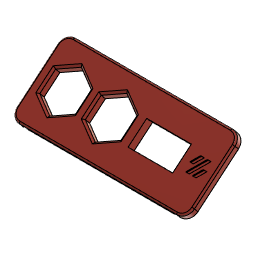
VoronSSD1306FrontScreen (Autodesk Fusion 360 design; units mm, degrees)
Autodesk Fusion 360 part; units mm, degrees
sketch "Skizze1" plane through (0, 0, 0) normal (0, 0, 1) x (1, 0, 0)
  line L0 (6, 0) -> (103, 0)
  line L1 (109, 6) -> (109, 38.6)
  line L2 (103, 44.6) -> (6, 44.6)
  line L3 (0, 38.6) -> (0, 6)
  arc A0 (6, 44.6) -> (0, 38.6) centre (6, 38.6) ccw
  arc A1 (109, 38.6) -> (103, 44.6) centre (103, 38.6) ccw
  arc A2 (103, 0) -> (109, 6) centre (103, 6) ccw
  arc A3 (0, 6) -> (6, 0) centre (6, 6) ccw
  circle A4 centre (7.9, 42.85) radius 2.35
  circle A5 centre (7.9, 1.75) radius 2.35
  circle A6 centre (101.1, 1.75) radius 2.35
  circle A7 centre (101.1, 42.85) radius 2.35
  line L4 (89.5, 34.3) -> (62, 34.3)
  line L5 (62, 34.3) -> (62, 6.3)
  line L6 (62, 6.3) -> (89.5, 6.3)
  line L7 (89.5, 6.3) -> (89.5, 34.3)
  line L8 (89.5, 34.3) -> (62, 6.3) construction
  line L9 (62, 34.3) -> (89.5, 6.3) construction
  line L10 (62, 29.8) -> (89.5, 29.8)
  line L11 (62, 14.8) -> (89.5, 14.8)
  line L12 (89.5, 9.8) -> (84.5, 9.8)
  line L13 (84.5, 9.8) -> (84.5, 6.3)
  line L14 (62, 9.8) -> (67, 9.8)
  line L15 (67, 9.8) -> (67, 6.3)
  line L16 (6, 15.9295) -> (17, 9.5787)
  line L17 (28, 28.6312) -> (17, 34.9821)
  line L18 (28, 15.9295) -> (28, 28.6312)
  line L19 (6, 28.6312) -> (6, 15.9295)
  line L20 (17, 9.5787) -> (28, 15.9295)
  line L21 (17, 34.9821) -> (6, 28.6312)
  line L22 (56, 28.6825) -> (45, 35.0333)
  line L23 (34, 28.6825) -> (34, 15.9808)
  line L24 (45, 35.0333) -> (34, 28.6825)
  line L25 (34, 15.9808) -> (45, 9.6299)
  line L26 (56, 15.9808) -> (56, 28.6825)
  line L27 (45, 9.6299) -> (56, 15.9808)
  line L28 (182, 0.3509) -> (171, 6.7017)
  line L29 (160, 0.3509) -> (160, -12.3509)
  line L30 (171, 6.7017) -> (160, 0.3509)
  line L31 (160, -12.3509) -> (171, -18.7017)
  line L32 (182, -12.3509) -> (182, 0.3509)
  line L33 (171, -18.7017) -> (182, -12.3509)
  line L34 (94.9685, 18.0639) -> (101.1584, 27.4799)
  line L35 (103.4205, 27.4799) -> (97.2309, 18.0639)
  line L36 (97.2309, 18.0639) -> (94.9685, 18.0639)
  line L37 (101.1584, 27.4799) -> (103.4205, 27.4799)
  line L38 (96.9893, 27.4799) -> (99.2516, 27.4799)
  line L39 (96.1573, 22.772) -> (93.8945, 22.772)
  line L40 (93.8945, 22.772) -> (96.9893, 27.4799)
  line L41 (99.2516, 27.4799) -> (96.1573, 22.772)
  line L42 (99.1374, 18.0639) -> (102.2323, 22.772)
  line L43 (104.4949, 22.772) -> (101.4002, 18.0639)
  line L44 (102.2323, 22.772) -> (104.4949, 22.772)
  line L45 (101.4002, 18.0639) -> (99.1374, 18.0639)
  point P0 (109, 0)
  point P1 (0, 44.6)
  point P2 (75.75, 20.3)
  point P3 (17, 22.2804)
  point P4 (45, 22.3316)
  point P5 (171, -6)
  point P6 (99.1947, 22.7719)
  point P7 (31.9611, 46.5087)
  dimension "d1" = 109
  dimension "d2" = 44.6
  dimension "d7" = 6
  dimension "d8" = 4.7
  dimension "d9" = 1.75
  dimension "d10" = 7.9
  dimension "d11" = 4.7
  dimension "d12" = 4.7
  dimension "d13" = 4.7
  dimension "d14" = 7.9
  dimension "d15" = 1.75
  dimension "d16" = 1.75
  dimension "d17" = 7.9
  dimension "d18" = 7.9
  dimension "d19" = 1.75
  dimension "d24" = 27.5
  dimension "d25" = 28
  dimension "d26" = 15
  dimension "d28" = 5
  dimension "d29" = 5
  dimension "d30" = 4.5
  dimension "d31" = 5
  dimension "d32" = 5
  dimension "d34" = 11
  dimension "d38" = 11
  dimension "d39" = 11
  dimension "d53" = 14.8
  dimension "d56" = 6
  dimension "d57" = 6
  dimension "d59" = 6
  constraint horizontal L0
  constraint vertical L1
  constraint horizontal L2
  constraint vertical L3
  constraint coincident P1 L2
  constraint coincident P1 L3
  constraint tangent L2 A0
  constraint tangent L3 A0
  constraint tangent L1 A1
  constraint tangent L2 A1
  constraint equal A0 A1
  constraint coincident P0 L0
  constraint coincident P0 L1
  constraint tangent L0 A2
  constraint tangent L1 A2
  constraint equal A0 A2
  constraint coincident origin L0
  constraint coincident origin L3
  constraint tangent L0 A3
  constraint tangent L3 A3
  constraint equal A0 A3
  constraint horizontal L4
  constraint perpendicular L4 L5
  constraint parallel L4 L6
  constraint parallel L5 L7
  constraint coincident L8 P2
  constraint coincident L9 P2
  constraint coincident L5 L10.start
  constraint coincident L7 L10.end
  constraint perpendicular L7 L10
  constraint coincident L5 L11.start
  constraint coincident L7 L11.end
  constraint perpendicular L7 L11
  constraint coincident L7 L12.start
  constraint perpendicular L7 L12
  constraint coincident L6 L13.end
  constraint perpendicular L6 L13
  constraint coincident L5 L14.start
  constraint perpendicular L5 L14
  constraint coincident L6 L15.end
  constraint perpendicular L6 L15
  measures "d1" distance of origin P0
  measures "d2" distance of origin P1
  measures "d7" radius of A0
  measures "d8" diameter of A4
  measures "d9" distance of L2 A4.centre
  measures "d10" distance of L3 A4.centre
  measures "d11" diameter of A5
  measures "d12" diameter of A6
  measures "d13" diameter of A7
  measures "d14" distance of L3 A5.centre
  measures "d15" distance of L0 A5.centre
  measures "d16" distance of L0 A6.centre
  measures "d17" distance of L1 A6.centre
  measures "d18" distance of L1 A7.centre
  measures "d19" distance of L2 A7.centre
  measures "d24" distance of L5.end L6.end
  measures "d25" distance of L4.end L5.end
  measures "d26" distance of L10 L11
  measures "d28" distance of L12.start L12.end
  measures "d29" distance of L11 L12
  measures "d30" distance of L4 L10
  measures "d31" distance of L14.start L14.end
  measures "d32" distance of L11 L14
  measures "d34" distance of P3 L18
  measures "d38" distance of P4 L26
  measures "d39" distance of P5 L32
  measures "d53" distance of L2 L10
  measures "d56" distance of L5 L26
  measures "d57" distance of L18 L23
  measures "d59" distance of L3 L19
sketch "Skizze1 (2)" plane through (0, 0, 0) normal (0, 0, 1) x (1, 0, 0) in component "SSD1306"
  line L0 (0, 0) -> (27.5, 0)
  line L1 (27.5, 0) -> (27.5, 27.5)
  line L2 (27.5, 27.5) -> (0, 27.5)
  line L3 (0, 27.5) -> (0, 0)
  circle A0 centre (3.3, 25.5) radius 1.05
  line L4 (0, 23.5) -> (27.5, 23.5)
  line L5 (27.5, 23.5) -> (27.5, 1.5)
  line L6 (27.5, 1.5) -> (0, 1.5)
  line L7 (0, 1.5) -> (0, 23.5)
  line L8 (8.75, 26.989) -> (18.75, 26.989)
  line L9 (18.75, 26.989) -> (18.75, 23.989)
  line L10 (18.75, 23.989) -> (8.75, 23.989)
  line L11 (8.75, 23.989) -> (8.75, 26.989)
  dimension "d1_1" = 27.5
  dimension "d2_1" = 27.5
  dimension "d3_1" = 2.1
  dimension "d4_1" = 2
  dimension "d5_1" = 3.3
  dimension "d6_1" = 22
  dimension "d7_1" = 4
  dimension "d8_1" = 10
  dimension "d9_1" = 3
  dimension "d10_1" = 8.75
  constraint horizontal L0
  constraint vertical L1
  constraint horizontal L2
  constraint vertical L3
  constraint coincident L0.start L3.end
  constraint horizontal L4
  constraint vertical L5
  constraint horizontal L6
  constraint vertical L7
  constraint coincident L3 L4.start
  constraint horizontal L8
  constraint vertical L9
  constraint horizontal L10
  constraint vertical L11
  measures "d1_1" distance of L0.start L0.end
  measures "d2_1" distance of L0.start L2.end
  measures "d3_1" diameter of A0
  measures "d4_1" distance of L2 A0.centre
  measures "d5_1" distance of L3 A0.centre
  measures "d6_1" distance of L4.start L6.end
  measures "d7_1" distance of L2 L4
  measures "d8_1" distance of L8.start L8.end
  measures "d9_1" distance of L8.start L10.end
  measures "d10_1" distance of L1 L9
extrude "Extrusion1" add sketch "Skizze1 (2)" along normal blind 1 contours L0 L1 L3 L6 | L1 L2 L3 L4 | L8 L9 L10 L11 makes body 1 at (19.7833, 25.5, 0) makes body 2 at (18.3333, 1, 0) in component "SSD1306"
extrude "Extrusion2" add sketch "Skizze1 (2)" along normal blind 2.7 contours L1 L3 L4 L5 L6 L7 bodies 1 2 in component "SSD1306"
extrude "Extrusion3" add sketch "Skizze1 (2)" against normal blind 8 contours L8 L9 L10 L11 bodies 1 in component "SSD1306"
move_body "Verschieben1" bodies 1 to x (1, 0, 0) y (0, 0, 1) z (0, -1, 0) at (13, -30, 74) in component "SSD1306"
move_body "Verschieben2" bodies 1 to x (1, 0, 0) y (0, 1, 0) z (0, 0, 1) at (25, 0, 0) in component "SSD1306"
move_body "Verschieben3" bodies 1 to x (1, 0, 0) y (0, 1, 0) z (0, 0, 1) at (136, 0, 0) in component "SSD1306"
extrude "Extrusion1'" add sketch "Skizze1" along normal blind 5.3 separate body contours L0 L1 L2 L3 A0 A1 A2 A3 A4 A5 A6 A7 | L0 A5 | L0 A6 | L2 A4 | L2 A7 | L4 L5 L7 L10 | L5 L7 L10 L11 | L5 L6 L7 L11 L12 L13 L14 L15 | L6 L7 L12 L13 | L5 L6 L14 L15 | L16 L17 L18 L19 L20 L21 | L22 L23 L24 L25 L26 L27 | L34 L35 L36 L37 | L38 L39 L40 L41 | L42 L43 L44 L45 picked at (8.2556, 2.4175) picked at (101.8272, 1.0977) picked at (8.6685, 42.3644) picked at (101.0598, 43.2344) makes body 3
extrude "Extrusion2'" cut sketch "Skizze1" along normal blind 4 contours L0 A5 | L0 A6 | L2 A4 | L2 A7 picked at (8.2556, 2.4175) picked at (101.8272, 1.0977) picked at (8.6685, 42.3644) picked at (101.0598, 43.2344) bodies 3
fillet "Abrundung2" radius 1 20 edges at (109, 22.3, 5.3) (107.2426, 42.8426, 5.3) (54.5, 44.6, 5.3) (1.7574, 42.8426, 5.3) (0, 22.3, 5.3) (1.7574, 1.7574, 5.3) (54.5, 0, 5.3) (107.2426, 1.7574, 5.3) (54.5, 0, 0) (6.1658, 44.6, 0) (1.7574, 42.8426, 0) (0, 22.3, 0) (1.7574, 1.7574, 0) (6.1658, 0, 0) (102.8342, 0, 0) (107.2426, 1.7574, 0) (109, 22.3, 0) (107.2426, 42.8426, 0) (102.8342, 44.6, 0) (54.5, 44.6, 0) on bodies 3
extrude "Extrusion3'" cut sketch "Skizze1" along normal blind 0.8 from surface at 4.5 contours L34 L35 L36 L37 | L38 L39 L40 L41 | L42 L43 L44 L45 bodies 3
extrude "Extrusion4" cut sketch "Skizze1" along normal blind 5.3 contours L5 L7 L10 L11 | L16 L17 L18 L19 L20 L21 | L22 L23 L24 L25 L26 L27 bodies 3
extrude "Extrusion5" cut sketch "Skizze1" along normal blind 4.9 contours L5 L6 L7 L11 L12 L13 L14 L15 bodies 3
extrude "Extrusion6" cut sketch "Skizze1" along normal blind 3.3 contours L4 L5 L7 L10 | L6 L7 L12 L13 | L5 L6 L14 L15 bodies 3
chamfer "Fase1" distance 1.2 angle 45 12 edges at (11.5, 31.8067, 5.3) (22.5, 31.8067, 5.3) (28, 22.2804, 5.3) (22.5, 12.7541, 5.3) (11.5, 12.7541, 5.3) (6, 22.2804, 5.3) (39.5, 31.8579, 5.3) (50.5, 31.8579, 5.3) (56, 22.3316, 5.3) (34, 22.3316, 5.3) (39.5, 12.8053, 5.3) (50.5, 12.8053, 5.3) on bodies 3
move_body "Verschieben1'" bodies 3 to x (1, 0, 0) y (0, 0.766044, 0.642788) z (0, -0.642788, 0.766044) at (0, 4.9148, 16.0966)
component "SSD1306" placed x (1, 0, 0) y (0, 1, 0) z (0, 0, 1) at (0, 0, 0)
equation "d10_1 = ( 17.5 / 2 ) * 1 mm"
equation "d50 = 5.3 mm - 2 mm"
named bodies: "SSD1306"
